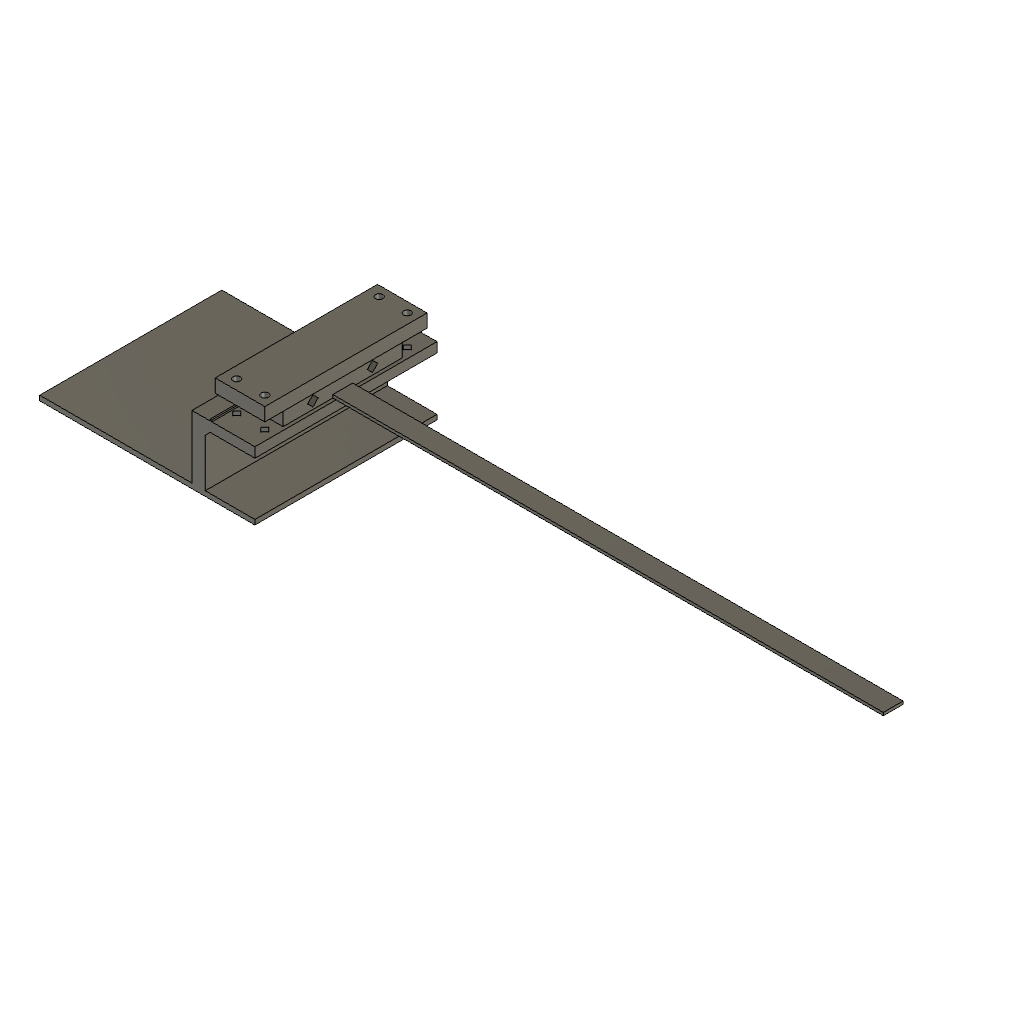
SkySafe_Laptop_Stand (Autodesk Fusion 360 design; units mm, degrees)
part number: 2026-10-11-03-39-07-411
part number: 2026-10-11-03-39-07-689
part number: 2026-10-11-03-39-07-890
part number: 2026-10-11-03-39-08-453
Autodesk Fusion 360 part; units mm, degrees
sketch "Table deck, back wall, gusset and thin laptop foot sketch" plane through (0, 0, 0) normal (0, 0, 1) x (1, 0, 0) in component "01 Laptop foot stand - PRINT ONE as exported"
  line L0 (-104, 0) -> (26, 0)
  line L1 (26, 0) -> (26, 3)
  line L2 (26, 3) -> (-4, 3)
  line L3 (-4, 3) -> (-4, 32)
  line L4 (-4, 32) -> (-1, 35)
  line L5 (-1, 35) -> (26, 35)
  line L6 (26, 35) -> (26, 41)
  line L7 (26, 41) -> (0, 41)
  line L8 (0, 41) -> (0, 42)
  line L9 (0, 42) -> (-1, 42)
  line L10 (-1, 42) -> (-1, 41)
  line L11 (-1, 41) -> (-12, 41)
  line L12 (-12, 41) -> (-12, 3)
  line L13 (-12, 3) -> (-104, 3)
  line L14 (-104, 3) -> (-104, 0)
extrude "Table deck, back wall, gusset and thin laptop foot" add sketch "Table deck, back wall, gusset and thin laptop foot sketch" along normal blind 110 makes body 1 in component "01 Laptop foot stand - PRINT ONE as exported"
ref_plane "WorkPlane1" through (0, 38, 0) normal (0, 1, 0) x (0, 0, 1) in component "01 Laptop foot stand - PRINT ONE as exported"
sketch "M3 diamond clearance (3, -43)" plane through (0, 38, 0) normal (0, 1, 0) x (1, 0, 0) in component "01 Laptop foot stand - PRINT ONE as exported"
  line L0 (0.5958, -98) -> (3, -95.5958)
  line L1 (3, -95.5958) -> (5.4042, -98)
  line L2 (5.4042, -98) -> (3, -100.4042)
  line L3 (3, -100.4042) -> (0.5958, -98)
extrude "Support-free M3 bore (3, -43)" cut sketch "M3 diamond clearance (3, -43)" along normal mid plane 6.1 bodies 1 in component "01 Laptop foot stand - PRINT ONE as exported"
ref_plane "WorkPlane2" through (0, 38, 0) normal (0, 1, 0) x (0, 0, 1) in component "01 Laptop foot stand - PRINT ONE as exported"
sketch "M3 diamond clearance (3, 43)" plane through (0, 38, 0) normal (0, 1, 0) x (1, 0, 0) in component "01 Laptop foot stand - PRINT ONE as exported"
  line L0 (0.5958, -12) -> (3, -9.5958)
  line L1 (3, -9.5958) -> (5.4042, -12)
  line L2 (5.4042, -12) -> (3, -14.4042)
  line L3 (3, -14.4042) -> (0.5958, -12)
extrude "Support-free M3 bore (3, 43)" cut sketch "M3 diamond clearance (3, 43)" along normal mid plane 6.1 bodies 1 in component "01 Laptop foot stand - PRINT ONE as exported"
ref_plane "WorkPlane3" through (0, 38, 0) normal (0, 1, 0) x (0, 0, 1) in component "01 Laptop foot stand - PRINT ONE as exported"
sketch "M3 diamond clearance (20, -43)" plane through (0, 38, 0) normal (0, 1, 0) x (1, 0, 0) in component "01 Laptop foot stand - PRINT ONE as exported"
  line L0 (17.5958, -98) -> (20, -95.5958)
  line L1 (20, -95.5958) -> (22.4042, -98)
  line L2 (22.4042, -98) -> (20, -100.4042)
  line L3 (20, -100.4042) -> (17.5958, -98)
extrude "Support-free M3 bore (20, -43)" cut sketch "M3 diamond clearance (20, -43)" along normal mid plane 6.1 bodies 1 in component "01 Laptop foot stand - PRINT ONE as exported"
ref_plane "WorkPlane4" through (0, 38, 0) normal (0, 1, 0) x (0, 0, 1) in component "01 Laptop foot stand - PRINT ONE as exported"
sketch "M3 diamond clearance (20, 43)" plane through (0, 38, 0) normal (0, 1, 0) x (1, 0, 0) in component "01 Laptop foot stand - PRINT ONE as exported"
  line L0 (17.5958, -12) -> (20, -9.5958)
  line L1 (20, -9.5958) -> (22.4042, -12)
  line L2 (22.4042, -12) -> (20, -14.4042)
  line L3 (20, -14.4042) -> (17.5958, -12)
extrude "Support-free M3 bore (20, 43)" cut sketch "M3 diamond clearance (20, 43)" along normal mid plane 6.1 bodies 1 in component "01 Laptop foot stand - PRINT ONE as exported"
sketch "Original cap sketch" plane through (0, 0, 0) normal (0, 0, 1) x (1, 0, 0) in component "02 Existing clamp cap - REUSE; do not print again"
  line L0 (-4, -49) -> (26, -49)
  line L1 (26, -49) -> (26, 49)
  line L2 (26, 49) -> (-4, 49)
  line L3 (-4, 49) -> (-4, -49)
extrude "Original cap" add sketch "Original cap sketch" along normal blind 8 separate body makes body 2 in component "02 Existing clamp cap - REUSE; do not print again"
ref_plane "WorkPlane1" through (0, 0, -0.05) normal (0, 0, 1) x (1, 0, 0) in component "02 Existing clamp cap - REUSE; do not print again"
sketch "Original cap clearance (3, -43) sketch" plane through (0, 0, -0.05) normal (0, 0, 1) x (1, 0, 0) in component "02 Existing clamp cap - REUSE; do not print again"
  circle A0 centre (3, -43) radius 2.2
extrude "Original cap clearance (3, -43)" cut sketch "Original cap clearance (3, -43) sketch" along normal blind 8.1 bodies 2 in component "02 Existing clamp cap - REUSE; do not print again"
ref_plane "WorkPlane2" through (0, 0, -0.05) normal (0, 0, 1) x (1, 0, 0) in component "02 Existing clamp cap - REUSE; do not print again"
sketch "Original cap clearance (3, 43) sketch" plane through (0, 0, -0.05) normal (0, 0, 1) x (1, 0, 0) in component "02 Existing clamp cap - REUSE; do not print again"
  circle A0 centre (3, 43) radius 2.2
extrude "Original cap clearance (3, 43)" cut sketch "Original cap clearance (3, 43) sketch" along normal blind 8.1 bodies 2 in component "02 Existing clamp cap - REUSE; do not print again"
ref_plane "WorkPlane3" through (0, 0, -0.05) normal (0, 0, 1) x (1, 0, 0) in component "02 Existing clamp cap - REUSE; do not print again"
sketch "Original cap clearance (20, -43) sketch" plane through (0, 0, -0.05) normal (0, 0, 1) x (1, 0, 0) in component "02 Existing clamp cap - REUSE; do not print again"
  circle A0 centre (20, -43) radius 2.2
extrude "Original cap clearance (20, -43)" cut sketch "Original cap clearance (20, -43) sketch" along normal blind 8.1 bodies 2 in component "02 Existing clamp cap - REUSE; do not print again"
ref_plane "WorkPlane4" through (0, 0, -0.05) normal (0, 0, 1) x (1, 0, 0) in component "02 Existing clamp cap - REUSE; do not print again"
sketch "Original cap clearance (20, 43) sketch" plane through (0, 0, -0.05) normal (0, 0, 1) x (1, 0, 0) in component "02 Existing clamp cap - REUSE; do not print again"
  circle A0 centre (20, 43) radius 2.2
extrude "Original cap clearance (20, 43)" cut sketch "Original cap clearance (20, 43) sketch" along normal blind 8.1 bodies 2 in component "02 Existing clamp cap - REUSE; do not print again"
ref_plane "WorkPlane1" through (0, 0, 41) normal (0, 0, 1) x (1, 0, 0) in component "REFERENCE ONLY - existing wing root and bending span"
sketch "Existing 24 x 72 x 10 mm root envelope sketch" plane through (0, 0, 41) normal (0, 0, 1) x (1, 0, 0) in component "REFERENCE ONLY - existing wing root and bending span"
  line L0 (0, -36) -> (24, -36)
  line L1 (24, -36) -> (24, 36)
  line L2 (24, 36) -> (0, 36)
  line L3 (0, 36) -> (0, -36)
extrude "Existing 24 x 72 x 10 mm root envelope" add sketch "Existing 24 x 72 x 10 mm root envelope sketch" along normal blind 10 separate body makes body 3 in component "REFERENCE ONLY - existing wing root and bending span"
ref_plane "WorkPlane2" through (-0.05, 0, 0) normal (1, 0, 0) x (0, 1, 0) in component "REFERENCE ONLY - existing wing root and bending span"
sketch "Existing skewer exit -18 sketch" plane through (-0.05, 0, 0) normal (1, 0, 0) x (0, 0, -1) in component "REFERENCE ONLY - existing wing root and bending span"
  line L0 (-45.5, -21.182) -> (-42.318, -18)
  line L1 (-42.318, -18) -> (-45.5, -14.818)
  line L2 (-45.5, -14.818) -> (-48.682, -18)
  line L3 (-48.682, -18) -> (-45.5, -21.182)
extrude "Existing skewer exit -18" cut sketch "Existing skewer exit -18 sketch" along normal blind 24.1 bodies 3 in component "REFERENCE ONLY - existing wing root and bending span"
ref_plane "WorkPlane3" through (-0.05, 0, 0) normal (1, 0, 0) x (0, 1, 0) in component "REFERENCE ONLY - existing wing root and bending span"
sketch "Existing skewer exit 18 sketch" plane through (-0.05, 0, 0) normal (1, 0, 0) x (0, 0, -1) in component "REFERENCE ONLY - existing wing root and bending span"
  line L0 (-45.5, 14.818) -> (-42.318, 18)
  line L1 (-42.318, 18) -> (-45.5, 21.182)
  line L2 (-45.5, 21.182) -> (-48.682, 18)
  line L3 (-48.682, 18) -> (-45.5, 14.818)
extrude "Existing skewer exit 18" cut sketch "Existing skewer exit 18 sketch" along normal blind 24.1 bodies 3 in component "REFERENCE ONLY - existing wing root and bending span"
ref_plane "WorkPlane4" through (0, 0, 41) normal (0, 0, 1) x (1, 0, 0) in component "REFERENCE ONLY - existing wing root and bending span"
sketch "Unloaded wing center envelope sketch" plane through (0, 0, 41) normal (0, 0, 1) x (1, 0, 0) in component "REFERENCE ONLY - existing wing root and bending span"
  line L0 (24, -6) -> (356.4, -6)
  line L1 (356.4, -6) -> (356.4, 6)
  line L2 (356.4, 6) -> (24, 6)
  line L3 (24, 6) -> (24, -6)
extrude "Unloaded wing center envelope" add sketch "Unloaded wing center envelope sketch" along normal blind 1.8 bodies 3 in component "REFERENCE ONLY - existing wing root and bending span"
component "02 Existing clamp cap - REUSE; do not print again" placed x (1, 0, 0) y (0, 1, 0) z (0, 0, 1) at (0, 0, 51)
component "01 Laptop foot stand - PRINT ONE as exported" placed x (1, 0, 0) y (0, 0, 1) z (0, -1, 0) at (0, 55, 0)
component "REFERENCE ONLY - existing wing root and bending span" placed x (1, 0, 0) y (0, 1, 0) z (0, 0, 1) at (0, 0, 0)
equation "standWidth = 110 mm" comment "Width along the wing chord"
equation "d2 = standWidth"
named bodies: "One native stand solid"
